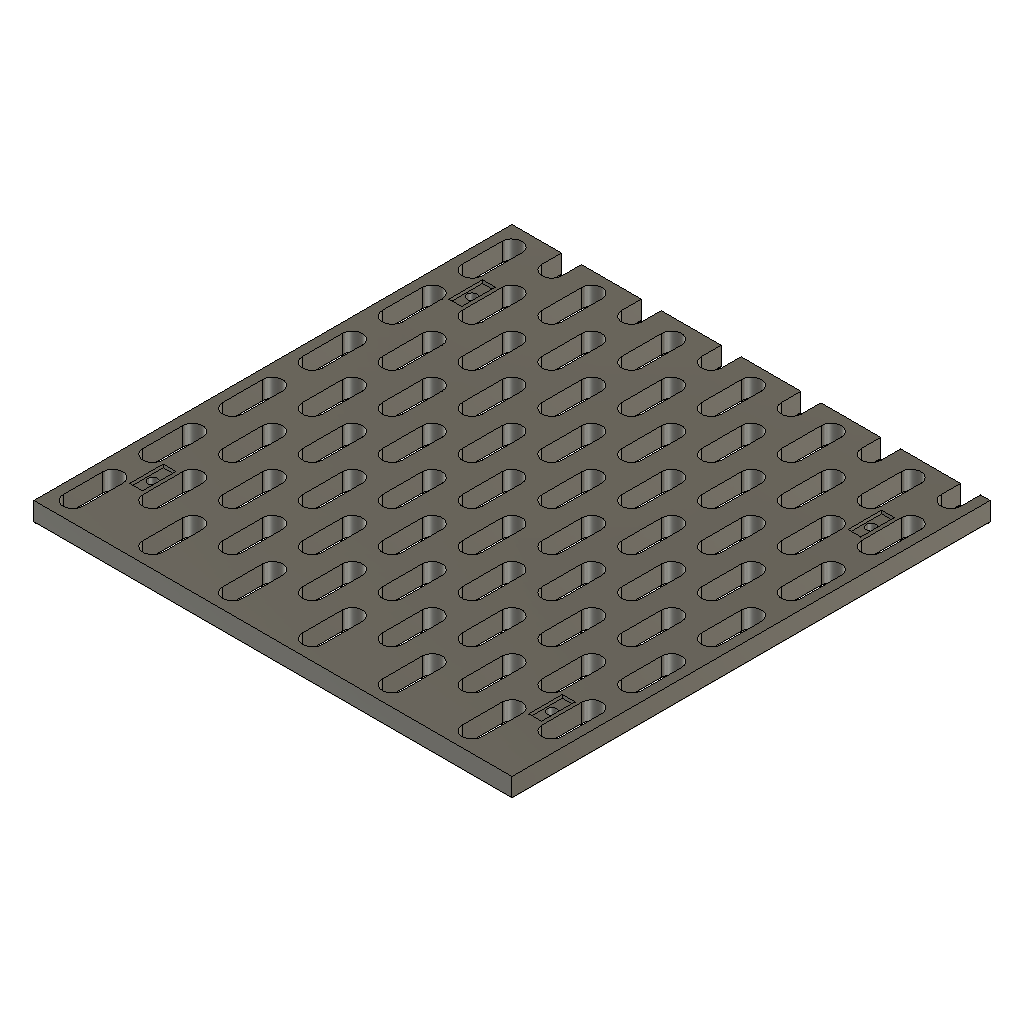
panel-bottom-edge-120 (Autodesk Fusion 360 design; units mm, degrees)
part number: 2026-10-29-11-18-20-185
part number: 2026-10-29-11-18-20-507
Autodesk Fusion 360 part; units mm, degrees
sketch "01 Panel blank sketch" plane through (0, 0, 0) normal (0, 0, 1) x (1, 0, 0) in component "Panel bottom-edge"
  line L0 (0.1, 0.1) -> (119.9, 0.1)
  line L1 (119.9, 0.1) -> (119.9, 119.9)
  line L2 (119.9, 119.9) -> (0.1, 119.9)
  line L3 (0.1, 119.9) -> (0.1, 0.1)
  dimension "d70" = 0.1
  dimension "d71" = 0.1
  dimension "d72" = 119.8
  dimension "d73" = 119.8
  constraint horizontal L0
  constraint vertical L1
  constraint horizontal L2
  constraint vertical L3
  measures "d70" horizontal distance of origin L0.start
  measures "d71" vertical distance of origin L0.start
  measures "d72" horizontal distance of L0.start L0.end
  measures "d73" vertical distance of L0.end L1.end
extrude "01 Panel blank" add sketch "01 Panel blank sketch" along normal blind 5 in component "Panel bottom-edge"
sketch "03 Complete A lattice constrained seed" plane through (0, 0, 0) normal (0, 0, 1) x (1, 0, 0) in component "Panel bottom-edge"
  line L0 (7.5, 5) -> (7.5, 15)
  arc A0 (7.5, 15) -> (2.5, 15) centre (5, 15) ccw
  line L1 (2.5, 15) -> (2.5, 5)
  arc A1 (2.5, 5) -> (7.5, 5) centre (5, 5) ccw
  line L2 (5, 5) -> (5, 15) construction
  line L3 (5, 5) -> (15, 5) construction
  dimension "d76" = 5
  dimension "d77" = 10
  dimension "d78" = 90
  dimension "d79" = 10
  dimension "d80" = 5
  dimension "d81" = 5
  constraint tangent L0 A0
  constraint tangent A0 L1
  constraint tangent L1 A1
  constraint tangent L0 A1
  constraint parallel L0 L1
  constraint horizontal L3
  measures "d76" diameter of A0
  measures "d77" distance of A1.centre A0.centre
  measures "d78" angle of L2 L3
  measures "d79" horizontal distance of A1.centre L3.end
  measures "d80" horizontal distance of origin A1.centre
  measures "d81" vertical distance of origin A1.centre
extrude "03 Complete A lattice through cut" cut sketch "03 Complete A lattice constrained seed" along normal blind 5 in component "Panel bottom-edge"
pattern_linear "03 Complete A lattice lattice" count 6 spacing 20 along (1, 0, 0) count 6 spacing 20 along (0, 1, 0) of "03 Complete A lattice through cut" in component "Panel bottom-edge"
sketch "04 B lattice with finished horizontal edges constrained seed" plane through (0, 0, 0) normal (0, 0, 1) x (1, 0, 0) in component "Panel bottom-edge"
  line L0 (17.5, 15) -> (17.5, 25)
  arc A0 (17.5, 25) -> (12.5, 25) centre (15, 25) ccw
  line L1 (12.5, 25) -> (12.5, 15)
  arc A1 (12.5, 15) -> (17.5, 15) centre (15, 15) ccw
  line L2 (15, 15) -> (15, 25) construction
  line L3 (15, 15) -> (25, 15) construction
  dimension "d88" = 5
  dimension "d89" = 10
  dimension "d90" = 90
  dimension "d91" = 10
  dimension "d92" = 15
  dimension "d93" = 15
  constraint tangent L0 A0
  constraint tangent A0 L1
  constraint tangent L1 A1
  constraint tangent L0 A1
  constraint parallel L0 L1
  constraint horizontal L3
  measures "d88" diameter of A0
  measures "d89" distance of A1.centre A0.centre
  measures "d90" angle of L2 L3
  measures "d91" horizontal distance of A1.centre L3.end
  measures "d92" horizontal distance of origin A1.centre
  measures "d93" vertical distance of origin A1.centre
extrude "04 B lattice with finished horizontal edges through cut" cut sketch "04 B lattice with finished horizontal edges constrained seed" along normal blind 5 in component "Panel bottom-edge"
pattern_linear "04 B lattice with finished horizontal edges lattice" count 6 spacing 20 along (1, 0, 0) count 6 spacing 20 along (0, 1, 0) of "04 B lattice with finished horizontal edges through cut" in component "Panel bottom-edge"
fillet "05 Rounded slot entrances and perimeter" radius 0.4 2 faces at (114.0711, 5.869, 0) (114.0711, 5.869, 0) in component "Panel bottom-edge"
sketch "06 M2 through bore sketch" plane through (0, 0, 0) normal (0, 0, 1) x (1, 0, 0) in component "Panel bottom-edge"
  circle A0 centre (10, 20) radius 1.2
  dimension "d102" = 10
  dimension "d103" = 20
  dimension "d104" = 2.4
  measures "d102" horizontal distance of origin A0.centre
  measures "d103" vertical distance of origin A0.centre
  measures "d104" diameter of A0
extrude "06 M2 through bore" cut sketch "06 M2 through bore sketch" along normal blind 5 in component "Panel bottom-edge"
sketch "07 Flush countersink sketch" plane through (0, 0, 0) normal (0, 0, 1) x (1, 0, 0) in component "Panel bottom-edge"
  circle A0 centre (10, 20) radius 2
  dimension "d107" = 10
  dimension "d108" = 20
  dimension "d109" = 4
  measures "d107" horizontal distance of origin A0.centre
  measures "d108" vertical distance of origin A0.centre
  measures "d109" diameter of A0
extrude "07 Flush countersink" cut sketch "07 Flush countersink sketch" along normal blind 0.8 draft -45 in component "Panel bottom-edge"
ref_plane "WorkPlane1" through (0, 0, 5) normal (0, 0, 1) x (1, 0, 0) in component "Panel bottom-edge"
sketch "08 Blind rear registration sketch" plane through (0, 0, 5) normal (0, 0, 1) x (1, 0, 0) in component "Panel bottom-edge"
  line L0 (8.4, 15.8) -> (11.6, 15.8)
  line L1 (11.6, 15.8) -> (11.6, 24.2)
  line L2 (11.6, 24.2) -> (8.4, 24.2)
  line L3 (8.4, 24.2) -> (8.4, 15.8)
  dimension "d114" = 8.4
  dimension "d115" = 15.8
  dimension "d116" = 3.2
  dimension "d117" = 8.4
  constraint horizontal L0
  constraint vertical L1
  constraint horizontal L2
  constraint vertical L3
  measures "d114" horizontal distance of origin L0.start
  measures "d115" vertical distance of origin L0.start
  measures "d116" horizontal distance of L0.start L0.end
  measures "d117" vertical distance of L0.end L1.end
extrude "08 Blind rear registration" cut sketch "08 Blind rear registration sketch" against normal blind 0.8 in component "Panel bottom-edge"
sketch "06 M2 through bore sketch (1)" plane through (0, 0, 0) normal (0, 0, 1) x (1, 0, 0) in component "Panel bottom-edge"
  circle A0 centre (10, 100) radius 1.2
  dimension "d120" = 10
  dimension "d121" = 100
  dimension "d122" = 2.4
  measures "d120" horizontal distance of origin A0.centre
  measures "d121" vertical distance of origin A0.centre
  measures "d122" diameter of A0
extrude "06 M2 through bore (1)" cut sketch "06 M2 through bore sketch (1)" along normal blind 5 in component "Panel bottom-edge"
sketch "07 Flush countersink sketch (1)" plane through (0, 0, 0) normal (0, 0, 1) x (1, 0, 0) in component "Panel bottom-edge"
  circle A0 centre (10, 100) radius 2
  dimension "d125" = 10
  dimension "d126" = 100
  dimension "d127" = 4
  measures "d125" horizontal distance of origin A0.centre
  measures "d126" vertical distance of origin A0.centre
  measures "d127" diameter of A0
extrude "07 Flush countersink (1)" cut sketch "07 Flush countersink sketch (1)" along normal blind 0.8 draft -45 in component "Panel bottom-edge"
ref_plane "WorkPlane2" through (0, 0, 5) normal (0, 0, 1) x (1, 0, 0) in component "Panel bottom-edge"
sketch "08 Blind rear registration sketch (1)" plane through (0, 0, 5) normal (0, 0, 1) x (1, 0, 0) in component "Panel bottom-edge"
  line L0 (8.4, 95.8) -> (11.6, 95.8)
  line L1 (11.6, 95.8) -> (11.6, 104.2)
  line L2 (11.6, 104.2) -> (8.4, 104.2)
  line L3 (8.4, 104.2) -> (8.4, 95.8)
  dimension "d132" = 8.4
  dimension "d133" = 95.8
  dimension "d134" = 3.2
  dimension "d135" = 8.4
  constraint horizontal L0
  constraint vertical L1
  constraint horizontal L2
  constraint vertical L3
  measures "d132" horizontal distance of origin L0.start
  measures "d133" vertical distance of origin L0.start
  measures "d134" horizontal distance of L0.start L0.end
  measures "d135" vertical distance of L0.end L1.end
extrude "08 Blind rear registration (1)" cut sketch "08 Blind rear registration sketch (1)" against normal blind 0.8 in component "Panel bottom-edge"
sketch "06 M2 through bore sketch (2)" plane through (0, 0, 0) normal (0, 0, 1) x (1, 0, 0) in component "Panel bottom-edge"
  circle A0 centre (110, 20) radius 1.2
  dimension "d138" = 110
  dimension "d139" = 20
  dimension "d140" = 2.4
  measures "d138" horizontal distance of origin A0.centre
  measures "d139" vertical distance of origin A0.centre
  measures "d140" diameter of A0
extrude "06 M2 through bore (2)" cut sketch "06 M2 through bore sketch (2)" along normal blind 5 in component "Panel bottom-edge"
sketch "07 Flush countersink sketch (2)" plane through (0, 0, 0) normal (0, 0, 1) x (1, 0, 0) in component "Panel bottom-edge"
  circle A0 centre (110, 20) radius 2
  dimension "d143" = 110
  dimension "d144" = 20
  dimension "d145" = 4
  measures "d143" horizontal distance of origin A0.centre
  measures "d144" vertical distance of origin A0.centre
  measures "d145" diameter of A0
extrude "07 Flush countersink (2)" cut sketch "07 Flush countersink sketch (2)" along normal blind 0.8 draft -45 in component "Panel bottom-edge"
ref_plane "WorkPlane3" through (0, 0, 5) normal (0, 0, 1) x (1, 0, 0) in component "Panel bottom-edge"
sketch "08 Blind rear registration sketch (2)" plane through (0, 0, 5) normal (0, 0, 1) x (1, 0, 0) in component "Panel bottom-edge"
  line L0 (108.4, 15.8) -> (111.6, 15.8)
  line L1 (111.6, 15.8) -> (111.6, 24.2)
  line L2 (111.6, 24.2) -> (108.4, 24.2)
  line L3 (108.4, 24.2) -> (108.4, 15.8)
  dimension "d150" = 108.4
  dimension "d151" = 15.8
  dimension "d152" = 3.2
  dimension "d153" = 8.4
  constraint horizontal L0
  constraint vertical L1
  constraint horizontal L2
  constraint vertical L3
  measures "d150" horizontal distance of origin L0.start
  measures "d151" vertical distance of origin L0.start
  measures "d152" horizontal distance of L0.start L0.end
  measures "d153" vertical distance of L0.end L1.end
extrude "08 Blind rear registration (2)" cut sketch "08 Blind rear registration sketch (2)" against normal blind 0.8 in component "Panel bottom-edge"
sketch "06 M2 through bore sketch (3)" plane through (0, 0, 0) normal (0, 0, 1) x (1, 0, 0) in component "Panel bottom-edge"
  circle A0 centre (110, 100) radius 1.2
  dimension "d156" = 110
  dimension "d157" = 100
  dimension "d158" = 2.4
  measures "d156" horizontal distance of origin A0.centre
  measures "d157" vertical distance of origin A0.centre
  measures "d158" diameter of A0
extrude "06 M2 through bore (3)" cut sketch "06 M2 through bore sketch (3)" along normal blind 5 in component "Panel bottom-edge"
sketch "07 Flush countersink sketch (3)" plane through (0, 0, 0) normal (0, 0, 1) x (1, 0, 0) in component "Panel bottom-edge"
  circle A0 centre (110, 100) radius 2
  dimension "d161" = 110
  dimension "d162" = 100
  dimension "d163" = 4
  measures "d161" horizontal distance of origin A0.centre
  measures "d162" vertical distance of origin A0.centre
  measures "d163" diameter of A0
extrude "07 Flush countersink (3)" cut sketch "07 Flush countersink sketch (3)" along normal blind 0.8 draft -45 in component "Panel bottom-edge"
ref_plane "WorkPlane4" through (0, 0, 5) normal (0, 0, 1) x (1, 0, 0) in component "Panel bottom-edge"
sketch "08 Blind rear registration sketch (3)" plane through (0, 0, 5) normal (0, 0, 1) x (1, 0, 0) in component "Panel bottom-edge"
  line L0 (108.4, 95.8) -> (111.6, 95.8)
  line L1 (111.6, 95.8) -> (111.6, 104.2)
  line L2 (111.6, 104.2) -> (108.4, 104.2)
  line L3 (108.4, 104.2) -> (108.4, 95.8)
  dimension "d168" = 108.4
  dimension "d169" = 95.8
  dimension "d170" = 3.2
  dimension "d171" = 8.4
  constraint horizontal L0
  constraint vertical L1
  constraint horizontal L2
  constraint vertical L3
  measures "d168" horizontal distance of origin L0.start
  measures "d169" vertical distance of origin L0.start
  measures "d170" horizontal distance of L0.start L0.end
  measures "d171" vertical distance of L0.end L1.end
extrude "08 Blind rear registration (3)" cut sketch "08 Blind rear registration sketch (3)" against normal blind 0.8 in component "Panel bottom-edge"
component "Panel bottom-edge" placed x (1, 0, 0) y (0, 1, 0) z (0, 0, 1) at (0, 0, 0)
equation "columns = 6" comment "Even integer 4..14; each cell is 20 mm"
equation "rows = 6" comment "Even integer 4..14"
equation "pitch = 20 mm" comment "Keep for dense SKADIS compatible lattice"
equation "panelWidth = columns * pitch" comment "Nominal module pitch X"
equation "panelHeight = rows * pitch" comment "Nominal module pitch Y"
equation "seamGap = 0.2 mm" comment "Physical envelope shrinks around fixed lattice"
equation "boardThickness = 5 mm" comment "Fit-test with real hooks"
equation "slotWidth = 5 mm" comment "Minimum throat width"
equation "slotHeight = 15 mm" comment "Minimum throat height"
equation "entryRadius = 0.4 mm" comment "Front slot and perimeter edge rounding"
equation "cornerRadius = 6 mm" comment "Plan-view panel corner rounding"
equation "hookClearance = 10 mm" comment "PROVISIONAL unobstructed depth behind board; carriers begin at its rear boundary"
equation "frameZ = carrierZ + carrierThickness" comment "Front extrusion datum"
equation "profileMouth = 6.28 mm" comment "User measured mouth"
equation "profileCavity = 11 mm" comment "User measured widest cavity"
equation "profileDepth = 6.2 mm" comment "User measured face-to-floor depth"
equation "profileFloor = 5.7 mm" comment "User estimate, lower confidence"
equation "profileLip = 1.5 mm" comment "Unmeasured; tentative comparable catalog value"
equation "profileTaperStart = profileDepth - ( profileCavity - profileFloor ) / 2" comment "Assumed 45-degree inner slopes"
equation "profileBore = 5 mm" comment "Unmeasured central bore, reference only"
equation "nutWidth = 8.8 mm" comment "Provisional low-profile METAL T-nut envelope, not old rectangular carrier"
equation "nutLength = 12 mm" comment "End-loaded anti-rotation metal nut envelope"
equation "nutThickness = 2.7 mm" comment "Thin nut reference; fit/load still unverified"
equation "jointLeg = 18 mm" comment "In-bay angle footprint"
equation "jointThickness = 3 mm" comment "Metal bracket thickness"
equation "jointDepth = 16 mm" comment "Bracket depth within 20 mm rail"
equation "sideScrewLength = 8 mm" comment "M5x8 reference; check against actual bracket and nut"
equation "wallTabHeight = 24 mm" comment "Tab along extrusion"
equation "wallTabReach = 22 mm" comment "Tab into open bay"
equation "wallAnchorClearance = 6.5 mm" comment "Placeholder wall anchor interface"
equation "wallDriverDiameter = 12 mm" comment "Clear tool envelope in open bays"
equation "keyDriverDiameter = 5 mm" comment "Short hex-key working-leg envelope"
equation "keyDriverReach = 20 mm" comment "Short hex-key working-leg reach"
equation "supportWidth = 3.2 mm" comment "Prototype blade; two perimeter lines need print review"
equation "supportLength = 12 mm" comment "Compression bearing length"
equation "hookEnvelopeWidth = 6 mm" comment "Conservative provisional continuous hook column"
equation "carrierThickness = 7 mm" comment "Room for captive M2 nut and stock M5x12"
equation "panelClearance = 2.4 mm" comment "M2 clearance"
equation "panelHeadPocket = 4 mm" comment "DIN965 3.8 mm head plus 0.1 mm recess"
equation "carrierHeadPocket = 9.4 mm" comment "DIN965 M5 9.2 mm head plus recess"
equation "carrierBore = 5.5 mm" comment "M5 clearance"
equation "tongueWidth = 2.8 mm" comment "Rear axial registration tongue"
equation "tongueLength = 8 mm" comment "Axial release registration"
equation "tongueDepth = 0.6 mm" comment "Tongue engagement"
equation "registerClearance = 0.2 mm" comment "Each side of printed tongue"
equation "carrierZ = boardThickness + hookClearance" comment "Rear hook cavity boundary"
equation "variantLeft = 0" comment "Finished edge flag; change by rebuilding variant, resize natively"
equation "variantRight = 0" comment "Finished edge flag; change by rebuilding variant, resize natively"
equation "variantBottom = 1" comment "Finished edge flag; change by rebuilding variant, resize natively"
equation "variantTop = 0" comment "Finished edge flag; change by rebuilding variant, resize natively"
equation "d70 = abs(( 0 mm ) + seamGap / 2)"
equation "d71 = abs(( 0 mm ) + seamGap / 2)"
equation "d72 = panelWidth - seamGap"
equation "d73 = panelHeight - seamGap"
equation "d74 = boardThickness"
equation "d76 = slotWidth"
equation "d77 = slotHeight - slotWidth"
equation "d79 = pitch / 2"
equation "d80 = abs(( 0 mm ) + pitch / 4)"
equation "d81 = abs(( ( 0 mm ) + pitch / 2 ) - ( slotHeight - slotWidth ) / 2)"
equation "d82 = boardThickness"
equation "d84 = columns"
equation "d85 = rows"
equation "d86 = pitch"
equation "d87 = pitch"
equation "d88 = slotWidth"
equation "d89 = slotHeight - slotWidth"
equation "d91 = pitch / 2"
equation "d92 = abs(( 0 mm ) + 3 * pitch / 4)"
equation "d93 = abs(( ( 0 mm ) + pitch * variantBottom ) - ( slotHeight - slotWidth ) / 2)"
equation "d94 = boardThickness"
equation "d96 = columns"
equation "d97 = rows + 1 - variantBottom - variantTop"
equation "d98 = pitch"
equation "d99 = pitch"
equation "d101 = entryRadius"
equation "d102 = abs(( 0 mm ) + pitch / 2)"
equation "d103 = abs(( 0 mm ) + pitch)"
equation "d104 = panelClearance"
equation "d105 = boardThickness"
equation "d107 = abs(( 0 mm ) + pitch / 2)"
equation "d108 = abs(( 0 mm ) + pitch)"
equation "d109 = panelHeadPocket"
equation "d110 = ( panelHeadPocket - panelClearance ) / 2"
equation "d112 = boardThickness"
equation "d114 = abs(( 0 mm ) + pitch / 2 - tongueWidth / 2 - registerClearance)"
equation "d115 = abs(( 0 mm ) + pitch - tongueLength / 2 - registerClearance)"
equation "d116 = tongueWidth + 2 * registerClearance"
equation "d117 = tongueLength + 2 * registerClearance"
equation "d118 = -tongueDepth - 0.2 mm"
equation "d120 = abs(( 0 mm ) + pitch / 2)"
equation "d121 = abs(( 0 mm ) + panelHeight - pitch)"
equation "d122 = panelClearance"
equation "d123 = boardThickness"
equation "d125 = abs(( 0 mm ) + pitch / 2)"
equation "d126 = abs(( 0 mm ) + panelHeight - pitch)"
equation "d127 = panelHeadPocket"
equation "d128 = ( panelHeadPocket - panelClearance ) / 2"
equation "d130 = boardThickness"
equation "d132 = abs(( 0 mm ) + pitch / 2 - tongueWidth / 2 - registerClearance)"
equation "d133 = abs(( 0 mm ) + panelHeight - pitch - tongueLength / 2 - registerClearance)"
equation "d134 = tongueWidth + 2 * registerClearance"
equation "d135 = tongueLength + 2 * registerClearance"
equation "d136 = -tongueDepth - 0.2 mm"
equation "d138 = abs(( 0 mm ) + panelWidth - pitch / 2)"
equation "d139 = abs(( 0 mm ) + pitch)"
equation "d140 = panelClearance"
equation "d141 = boardThickness"
equation "d143 = abs(( 0 mm ) + panelWidth - pitch / 2)"
equation "d144 = abs(( 0 mm ) + pitch)"
equation "d145 = panelHeadPocket"
equation "d146 = ( panelHeadPocket - panelClearance ) / 2"
equation "d148 = boardThickness"
equation "d150 = abs(( 0 mm ) + panelWidth - pitch / 2 - tongueWidth / 2 - registerClearance)"
equation "d151 = abs(( 0 mm ) + pitch - tongueLength / 2 - registerClearance)"
equation "d152 = tongueWidth + 2 * registerClearance"
equation "d153 = tongueLength + 2 * registerClearance"
equation "d154 = -tongueDepth - 0.2 mm"
equation "d156 = abs(( 0 mm ) + panelWidth - pitch / 2)"
equation "d157 = abs(( 0 mm ) + panelHeight - pitch)"
equation "d158 = panelClearance"
equation "d159 = boardThickness"
equation "d161 = abs(( 0 mm ) + panelWidth - pitch / 2)"
equation "d162 = abs(( 0 mm ) + panelHeight - pitch)"
equation "d163 = panelHeadPocket"
equation "d164 = ( panelHeadPocket - panelClearance ) / 2"
equation "d166 = boardThickness"
equation "d168 = abs(( 0 mm ) + panelWidth - pitch / 2 - tongueWidth / 2 - registerClearance)"
equation "d169 = abs(( 0 mm ) + panelHeight - pitch - tongueLength / 2 - registerClearance)"
equation "d170 = tongueWidth + 2 * registerClearance"
equation "d171 = tongueLength + 2 * registerClearance"
equation "d172 = -tongueDepth - 0.2 mm"
